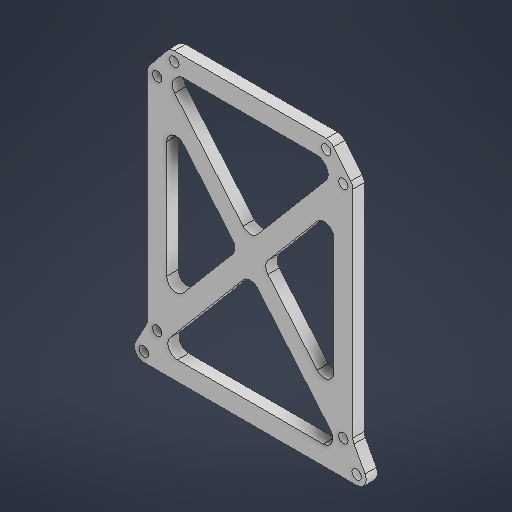
# Autodesk Inventor part: Rpi_Rplidar_mount
Saved by Autodesk Inventor 2026.3 (Build 303398000, 398)
## iProperties
Created: 2026-07-17
Part Number: Rpi_Rplidar_mount
Material: Generic
Document SubType Name: Modeling
Designer: nose
Density: 1 g/cm^3
Appearance: Default
Author: nose
Autodesk Inventor part; units mm, degrees
ref_plane "YZ Plane" through (0, 0, 0) normal (1, 0, 0) x (0, 1, 0)
ref_plane "XZ Plane" through (0, 0, 0) normal (0, 1, 0) x (-1, 0, 0)
ref_plane "XY Plane" through (0, 0, 0) normal (0, 0, 1) x (1, 0, 0)
sketch "Sketch1" plane through (0, 0, 0) normal (0, 0, 1) x (1, 0, 0)
  line L0 (24.5, -29) -> (-24.5, -29) construction
  line L1 (-24.5, -29) -> (-24.5, 29) construction
  line L2 (-24.5, 29) -> (24.5, 29) construction
  line L3 (24.5, 29) -> (24.5, -29) construction
  line L4 (24.5, -29) -> (-24.5, 29) construction
  line L5 (-24.5, -29) -> (24.5, 29) construction
  circle A0 centre (-24.5, 29) radius 1.25
  circle A1 centre (24.5, 29) radius 1.25
  line L6 (-28, -35.5) -> (28, -35.5) construction
  line L7 (28, -35.5) -> (20, 34.5446) construction
  line L8 (20, 34.5446) -> (-20, 34.5446) construction
  circle A2 centre (24.5, -29) radius 1.25
  circle A3 centre (-24.5, -29) radius 1.25
  line L9 (-28, -35.5) -> (-20, 34.5446) construction
  circle A4 centre (-20, 34.5446) radius 1.25
  circle A5 centre (20, 34.5446) radius 1.25
  circle A6 centre (-28, -35.5) radius 1.25
  circle A7 centre (28, -35.5) radius 1.25
  line L10 (-20, 34.5446) -> (-24.5, 29)
  line L11 (-24.5, 29) -> (-24.5, -29)
  line L12 (-24.5, -29) -> (-28, -35.5)
  line L13 (20, 34.5446) -> (24.5, 29)
  line L14 (24.5, 29) -> (24.5, -29)
  line L15 (24.5, -29) -> (28, -35.5)
  line L16 (28, -35.5) -> (-28, -35.5)
  line L17 (-20, 34.5446) -> (20, 34.5446)
  line L18 (-22, 28.1132) -> (-18.8092, 32.0446)
  line L19 (-18.8092, 32.0446) -> (18.8092, 32.0446)
  line L20 (18.8092, 32.0446) -> (22, 28.1132)
  line L21 (22, 28.1132) -> (22, -29.6303)
  line L22 (22, -29.6303) -> (23.8145, -33)
  line L23 (23.8145, -33) -> (-23.8145, -33)
  line L24 (-23.8145, -33) -> (-22, -29.6303)
  line L25 (-22, -29.6303) -> (-22, 28.1132)
  line L26 (-27, 29.8868) -> (-21.1908, 37.0446)
  line L27 (-21.1908, 37.0446) -> (21.1908, 37.0446)
  line L28 (21.1908, 37.0446) -> (27, 29.8868)
  line L29 (27, 29.8868) -> (27, -28.3697)
  line L30 (27, -28.3697) -> (32.1855, -38)
  line L31 (32.1855, -38) -> (-32.1855, -38)
  line L32 (-32.1855, -38) -> (-27, -28.3697)
  line L33 (-27, -28.3697) -> (-27, 29.8868)
  line L34 (24.5, -29) -> (-24.5, 29) construction
  line L35 (24.5, 29) -> (-24.5, -29) construction
  line L36 (26.2021, -27.1409) -> (-22.5903, 30.6134)
  line L37 (22.8892, -30.9672) -> (-26.4097, 27.3866)
  line L38 (26.4097, 27.3866) -> (-22.5903, -30.6134)
  line L39 (22.5903, 30.6134) -> (-26.4097, -27.3866)
  point P0 (0, 0)
  point P1 (0, -7.5)
  point P2 (0, 3.8739)
  point P3 (-21.2543, 29.032)
  point P4 (-22, 22.167)
  point P5 (-3.2727, 0)
  point P6 (-22, -22.167)
  point P7 (-22.4223, -30.4145)
  point P8 (0, -3.8739)
  point P9 (22.4223, -30.4145)
  point P10 (22, -22.167)
  point P11 (3.2727, 0)
  point P12 (22, 22.167)
  point P13 (21.2543, 29.032)
  dimension "d0" = 49
  dimension "d1" = 58
  dimension "d2" = 2.5
  dimension "d7" = 2.5
  dimension "d9" = 56
  dimension "d10" = 70.5
  dimension "d11" = 2.5
  dimension "d12" = 2.5
  dimension "d13" = 70.5
  dimension "d14" = 40
  dimension "d15" = 2.5
  dimension "d16" = 2.5
  dimension "d17" = 2.5
  dimension "d18" = 2.5
  dimension "d19" = 28
  dimension "d20" = 28
  dimension "d21" = 7.5
  dimension "d22" = 2.5
  dimension "d23" = 2.5
  dimension "d26" = 2.5
  dimension "d27" = 2.5
  dimension "d28" = 2.5
  dimension "d29" = 2.5
  constraints: 80 end point, 8 centre point, 7 coincident, 7 parallel, 4 collinear, 2 horizontal, 2 midpoint, 1 perpendicular, 1 vertical, 14 other
  measures "d0" distance of L1.end L2.end
  measures "d1" distance of L0.end L1.end
  measures "d2" diameter of A0
  measures "d7" diameter of A1
  measures "d9" distance of L6.start L6.end
  measures "d10" distance of L6.end L7.end
  measures "d11" diameter of A2
  measures "d12" diameter of A3
  measures "d13" distance of L8.end L6.start
  measures "d14" distance of L7.end L8.end
  measures "d15" diameter of A4
  measures "d16" diameter of A5
  measures "d17" diameter of A6
  measures "d18" diameter of A7
  measures "d19" horizontal distance of L6.end point (0, -7.5)
  measures "d20" horizontal distance of L6.end point (0, -7.5)
  measures "d21" distance of point (0, -7.5) point (0, 0)
  measures "d22" distance between parallel lines of L10 L18
  measures "d23" distance between parallel lines of L10 L26
  measures "d26" distance between parallel lines of L34 L36
  measures "d27" distance between parallel lines of L34 L37
  measures "d28" distance between parallel lines of L35 L38
  measures "d29" distance between parallel lines of L35 L39
extrude "Extrusion1" add sketch "Sketch1" along normal blind 3 contours A0 L10 A4 L17 A5 L13 A1 L14 L38 L21 L20 L19 L18 L25 L37 L11 | L37 L25 L39 L11 | L39 L25 L24 L23 L22 L21 L36 L14 A2 L15 A7 L16 A6 L12 A3 L11 | L25 L18 L36 L39 L37 | L39 L37 L38 L24 L25 | L39 L36 L38 L37 | L38 L36 L21 L22 L37 | L39 L20 L21 L38 L36 | L21 L38 L14 L36 | L26 L27 L28 L29 L30 L31 L32 L33
fillet "Fillet1" radius 2.5 6 edges at (-32.1855, -38, 1.5) (32.1855, -38, 1.5) (27, 29.8868, 1.5) (21.1908, 37.0446, 1.5) (-21.1908, 37.0446, 1.5) (-27, 29.8868, 1.5)
fillet "Fillet2" radius 2.5 18 edges at (18.8092, 32.0446, 1.5) (21.2543, 29.032, 1.5) (-18.8092, 32.0446, 1.5) (-21.2543, 29.032, 1.5) (0, 3.8739, 1.5) (3.2727, 0, 1.5) (-3.2727, 0, 1.5) (0, -3.8739, 1.5) (22, 22.167, 1.5) (-22, 22.167, 1.5) (-22, -22.167, 1.5) (22, -22.167, 1.5) (-23.8145, -33, 1.5) (-22.4223, -30.4145, 1.5) (23.8145, -33, 1.5) (22.4223, -30.4145, 1.5) (27, -28.3697, 1.5) (-27, -28.3697, 1.5)
equation "\"d0\" = rpi_hole_width"
equation "\"d2\" = rpi_hole_dia"
equation "\"d7\" = rpi_hole_dia"
equation "\"d11\" = rpi_hole_dia"
equation "\"d12\" = rpi_hole_dia"
equation "\"d15\" = lidar_hole_dia"
equation "\"d16\" = lidar_hole_dia"
equation "\"d17\" = lidar_hole_dia"
equation "\"d18\" = lidar_hole_dia"
equation "\"d21\" = lidar_middle_offset"
equation "\"d22\" = frame_width"
equation "\"d23\" = frame_width"
equation "\"d26\" = frame_width"
equation "\"d27\" = frame_width"
equation "\"d28\" = frame_width"
equation "\"d29\" = frame_width"
equation "\"rpi_hole_dia\" = 2.5"
equation "\"rpi_hole_width\" = 49"
equation "\"rpi_hole_length\" = 58"
equation "\"lidar_hole_dia\" = 2.5"
equation "\"lidar_middle_offset\" = 7.5"
equation "\"frame_width\" = 2.5"
body "Solid1"
